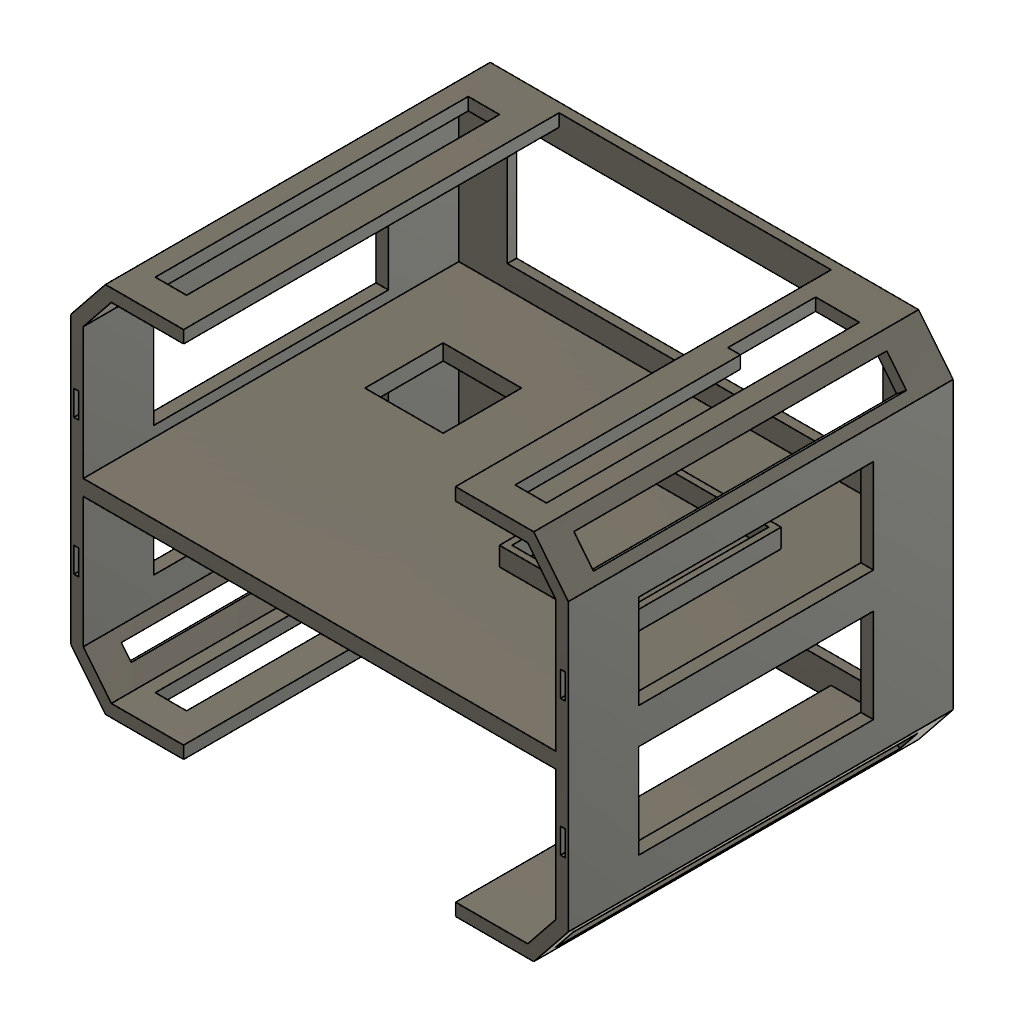
CAD_PicoHead (Autodesk Fusion 360 archive; units mm, degrees)
design "Side"
part number: 2026-11-01-21-09-07-078
Autodesk Fusion 360 part; units mm, degrees
(part 1 of 2)
sketch "Sketch1" plane through (0, 0, 0) normal (0, 0, 1) x (1, 0, 0)
  line L0 (31.9907, 26.2881) -> (20.9421, 12.4971)
  line L1 (31.9907, 26.2881) -> (31.9907, 117.6911)
  line L2 (31.9907, 117.6911) -> (20.9421, 131.4821)
  line L3 (20.9421, 131.4821) -> (-4.0579, 131.4821)
  line L4 (20.9614, 12.4971) -> (-115.9606, 12.4971)
  line L5 (-115.9606, 12.4971) -> (-127.0093, 26.2881)
  line L6 (-127.0093, 26.2881) -> (-127.0093, 117.6911)
  line L7 (-127.0093, 117.6911) -> (-115.9606, 131.4821)
  line L8 (-90.9606, 131.4821) -> (-115.9606, 131.4821)
  line L9 (-90.9606, 127.4821) -> (-114.0398, 127.4821)
  line L10 (-123.0093, 116.2864) -> (-114.0398, 127.4821)
  line L11 (-123.0093, 27.6928) -> (-123.0093, 116.2864)
  line L12 (-114.0398, 16.4971) -> (-123.0093, 27.6928)
  line L13 (19.0213, 16.4971) -> (-114.0398, 16.4971)
  line L14 (20.9614, 131.4821) -> (20.9614, 131.4579)
  line L15 (-90.9606, 131.4821) -> (-90.9606, 127.4821)
  line L16 (19.0213, 127.4821) -> (-4.0579, 127.4821)
  line L17 (27.9907, 116.2864) -> (19.0213, 127.4821)
  line L18 (27.9907, 27.6928) -> (27.9907, 116.2864)
  line L19 (27.9907, 27.6928) -> (19.0213, 16.4971)
  line L20 (-4.0579, 131.4821) -> (-4.0579, 127.4821)
  dimension "d35" = 17.671
  dimension "d36" = 17.671
  dimension "d37" = 141.3
  dimension "d38" = 141.3
  dimension "d39" = 25
  dimension "d79" = 17.671
  dimension "d83" = 128.7
  dimension "d84" = 91.403
  dimension "d85" = 25
  dimension "d138" = 159
  dimension "d140" = 4
  dimension "d141" = 4
  dimension "d142" = 4
  dimension "d143" = 4
  dimension "d144" = 4
  dimension "d145" = 4
  dimension "d146" = 4
  dimension "d147" = 4
  dimension "d148" = 4
  constraint vertical L1
  constraint perpendicular L1 L3
  constraint horizontal L4
  constraint perpendicular L3 L14
  constraint perpendicular L9 L15
  constraint coincident L2 L14.end
  constraint perpendicular L16 L20
  measures "d35" distance of L1.end L2.end
  measures "d36" distance of L0.end L0.start
  measures "d37" angle of L0 L1
  measures "d38" angle of L1 L2
  measures "d39" distance of L3.end L2.end
  measures "d79" distance of L4.end L5.end
  measures "d83" angle of L4 L5
  measures "d84" distance of L5.end L6.end
  measures "d85" distance of L7.end L8.start
  measures "d138" distance of L1 L6
  measures "d140" distance of L8 L9
  measures "d141" distance of L7 L10
  measures "d142" distance of L6 L11
  measures "d143" distance of L5 L12
  measures "d144" distance of L4 L13
  measures "d145" distance of L3 L16
  measures "d146" distance of L2 L17
  measures "d147" distance of L1 L18
  measures "d148" distance of L0 L19
extrude "Extrude1" add sketch "Sketch1" along normal blind 120
sketch "Sketch12" plane through (-127.0093, 0, 0) normal (-1, 0, 0) x (0, 0, 1)
  line L0 (0, 117.6911) -> (0, 26.2881)
  line L1 (0, 26.2881) -> (120, 26.2881)
  line L2 (120, 26.2881) -> (120, 117.6911)
  line L3 (120, 117.6911) -> (0, 117.6911)
  line L4 (22.5, 107.6911) -> (97.5, 107.6911)
  line L5 (97.5, 107.6911) -> (97.5, 77.6911)
  line L6 (97.5, 77.6911) -> (22.5, 77.6911)
  line L7 (22.5, 77.6911) -> (22.5, 107.6911)
  line L8 (60, 117.6911) -> (60, 26.2881) construction
  line L9 (97.5, 66.2881) -> (22.5, 66.2881)
  line L10 (22.5, 66.2881) -> (22.5, 36.2881)
  line L11 (22.5, 36.2881) -> (97.5, 36.2881)
  line L12 (97.5, 36.2881) -> (97.5, 66.2881)
  dimension "d87" = 75
  dimension "d88" = 30
  dimension "d89" = 37.5
  dimension "d90" = 75
  dimension "d91" = 30
  dimension "d93" = 10
  dimension "d94" = 10
  constraint horizontal L4
  constraint vertical L5
  constraint horizontal L6
  constraint vertical L7
  constraint midpoint L3 L8.start
  constraint midpoint L1 L8.end
  constraint horizontal L9
  constraint vertical L10
  constraint horizontal L11
  constraint vertical L12
  measures "d87" distance of L4.start L4.end
  measures "d88" distance of L4.start L6.end
  measures "d89" distance of L5 L8
  measures "d90" distance of L9.start L9.end
  measures "d91" distance of L9.start L11.end
  measures "d93" distance of L3 L4
  measures "d94" distance of L1 L11
extrude "Extrude11" cut sketch "Sketch12" against normal blind 33 contours L4 L5 L6 L7 | L9 L10 L11 L12
sketch "Sketch13" plane through (31.9907, 0, 0) normal (1, 0, 0) x (0, 0, -1)
  line L0 (0, 26.2881) -> (0, 117.6911)
  line L1 (0, 117.6911) -> (-120, 117.6911)
  line L2 (-120, 117.6911) -> (-120, 26.2881)
  line L3 (-120, 26.2881) -> (0, 26.2881)
  line L4 (-60, 117.6911) -> (-60, 26.2881) construction
  line L5 (-97.5, 107.6911) -> (-22.5, 107.6911)
  line L6 (-22.5, 107.6911) -> (-22.5, 77.6911)
  line L7 (-22.5, 77.6911) -> (-97.5, 77.6911)
  line L8 (-97.5, 77.6911) -> (-97.5, 107.6911)
  line L9 (-22.5, 36.2881) -> (-97.5, 36.2881)
  line L10 (-97.5, 36.2881) -> (-97.5, 66.2881)
  line L11 (-97.5, 66.2881) -> (-22.5, 66.2881)
  line L12 (-22.5, 66.2881) -> (-22.5, 36.2881)
  line L13 (0, 26.2881) -> (0, 117.6911)
  line L14 (0, 117.6911) -> (-120, 117.6911)
  line L15 (-120, 117.6911) -> (-120, 26.2881)
  line L16 (-120, 26.2881) -> (0, 26.2881)
  dimension "d97" = 75
  dimension "d98" = 30
  dimension "d99" = 37.5
  dimension "d100" = 10
  dimension "d101" = 75
  dimension "d102" = 37.5
  dimension "d103" = 10
  dimension "d104" = 30
  constraint midpoint L1 L4.start
  constraint midpoint L3 L4.end
  constraint horizontal L5
  constraint vertical L6
  constraint horizontal L7
  constraint vertical L8
  constraint horizontal L9
  constraint vertical L10
  constraint horizontal L11
  constraint vertical L12
  measures "d97" distance of L5.start L5.end
  measures "d98" distance of L5.start L7.end
  measures "d99" distance of L4 L6
  measures "d100" distance of L1 L5
  measures "d101" distance of L9.start L9.end
  measures "d102" distance of L4 L12
  measures "d103" distance of L3 L9
  measures "d104" distance of L9.start L11.end
extrude "Extrude12" cut sketch "Sketch13" against normal blind 20 contours L5 L6 L7 L8 | L9 L10 L11 L12
sketch "Sketch14" plane through (0, 131.4821, 0) normal (0, 1, 0) x (-1, 0, 0)
  line L0 (-45.9614, 0) -> (-20.9614, 0)
  line L1 (-20.9614, 0) -> (-20.9614, 120)
  line L2 (-20.9614, 120) -> (-45.9614, 120)
  line L3 (110, 10) -> (100, 10)
  line L4 (100, 10) -> (100, 110)
  line L5 (100, 110) -> (110, 110)
  line L6 (110, 110) -> (110, 10)
  line L7 (-20.9421, 0) -> (4.0579, 0)
  line L8 (4.0579, 0) -> (4.0579, 120)
  line L9 (4.0579, 120) -> (-20.9421, 120)
  line L10 (-20.9421, 120) -> (-20.9421, 0)
  line L11 (-5, 10) -> (-15, 10)
  line L12 (-15, 10) -> (-15, 110)
  line L13 (-15, 110) -> (-5, 110)
  line L14 (-5, 110) -> (-5, 10)
  constraint horizontal L3
  constraint vertical L4
  constraint horizontal L5
  constraint vertical L6
  constraint horizontal L11
  constraint vertical L12
  constraint horizontal L13
  constraint vertical L14
extrude "Extrude13" cut sketch "Sketch14" against normal blind 10 contours L3 L4 L5 L6 | L11 L12 L13 L14
sketch "Sketch15" plane through (76.913, 61.6189, 0) normal (0.78043, 0.625243, 0) x (0, 0, -1)
  line L0 (0, 56.2046) -> (0, 73.8756)
  line L1 (0, 73.8756) -> (-120, 73.8756)
  line L2 (-120, 73.8756) -> (-120, 56.2046)
  line L3 (-120, 56.2046) -> (0, 56.2046)
  line L4 (0, 71.8477) -> (0, 89.5187)
  line L5 (0, 89.5187) -> (-120, 89.5187)
  line L6 (-120, 89.5187) -> (-120, 71.8477)
  line L7 (-120, 71.8477) -> (0, 71.8477)
  line L8 (-110, 85) -> (-10, 85)
  line L9 (-10, 85) -> (-10, 75)
  line L10 (-10, 75) -> (-110, 75)
  line L11 (-110, 75) -> (-110, 85)
  constraint horizontal L8
  constraint vertical L9
  constraint horizontal L10
  constraint vertical L11
extrude "Extrude14" cut sketch "Sketch15" against normal blind 40 contours L8 L9 L10 L11
sketch "Sketch16" plane through (-134.7861, 107.984, 0) normal (-0.78043, 0.625243, 0) x (0, 0, 1)
  line L0 (0, 30.1091) -> (0, 12.4381)
  line L1 (0, 12.4381) -> (120, 12.4381)
  line L2 (120, 12.4381) -> (120, 30.1091)
  line L3 (120, 30.1091) -> (0, 30.1091)
  line L4 (10, 25) -> (110, 25)
  line L5 (110, 25) -> (110, 15)
  line L6 (110, 15) -> (10, 15)
  line L7 (10, 15) -> (10, 25)
  constraint horizontal L4
  constraint vertical L5
  constraint horizontal L6
  constraint vertical L7
extrude "Extrude15" cut sketch "Sketch16" against normal blind 20 contours L4 L5 L6 L7
sketch "Sketch17" plane through (6.6572, -5.3334, 0) normal (0.78043, -0.625243, 0) x (0, 0, -1)
  line L0 (0, 38.4901) -> (0, 56.1611)
  line L1 (0, 56.1611) -> (-120, 56.1611)
  line L2 (-120, 56.1611) -> (-120, 38.4901)
  line L3 (-120, 38.4901) -> (0, 38.4901)
  line L4 (0, 22.847) -> (0, 40.518)
  line L5 (0, 40.518) -> (-120, 40.518)
  line L6 (-120, 40.518) -> (-120, 22.847)
  line L7 (-120, 22.847) -> (0, 22.847)
  line L8 (-115, 35) -> (-5, 35)
  line L9 (-5, 35) -> (-5, 26)
  line L10 (-5, 26) -> (-115, 26)
  line L11 (-115, 26) -> (-115, 35)
  constraint horizontal L8
  constraint vertical L9
  constraint horizontal L10
  constraint vertical L11
extrude "Extrude16" cut sketch "Sketch17" against normal blind 20 contours L8 L9 L10 L11
sketch "Sketch18" plane through (-64.5303, -51.6985, 0) normal (-0.78043, -0.625243, 0) x (0, 0, 1)
  line L0 (0, 99.9276) -> (0, 82.2566)
  line L1 (0, 82.2566) -> (120, 82.2566)
  line L2 (120, 82.2566) -> (120, 99.9276)
  line L3 (120, 99.9276) -> (0, 99.9276)
  line L4 (10, 95) -> (110, 95)
  line L5 (110, 95) -> (110, 90)
  line L6 (110, 90) -> (10, 90)
  line L7 (10, 90) -> (10, 95)
  constraint horizontal L4
  constraint vertical L5
  constraint horizontal L6
  constraint vertical L7
extrude "Extrude17" cut sketch "Sketch18" against normal blind 25 contours L4 L5 L6 L7
sketch "Sketch19" plane through (0, 0, 0) normal (0, 0, -1) x (-1, 0, 0)
  line L0 (-20.9421, 12.4971) -> (115.9606, 12.4971)
  line L1 (115.9606, 12.4971) -> (127.0093, 26.2881)
  line L2 (127.0093, 26.2881) -> (127.0093, 117.6911)
  line L3 (127.0093, 117.6911) -> (115.9606, 131.4821)
  line L4 (115.9606, 131.4821) -> (90.9606, 131.4821)
  line L5 (90.9606, 131.4821) -> (90.9606, 127.4821)
  line L6 (90.9606, 127.4821) -> (114.0398, 127.4821)
  line L7 (114.0398, 127.4821) -> (123.0093, 116.2864)
  line L8 (123.0093, 116.2864) -> (123.0093, 27.6928)
  line L9 (123.0093, 27.6928) -> (114.0398, 16.4971)
  line L10 (114.0398, 16.4971) -> (-19.0213, 16.4971)
  line L11 (-45.9614, 131.4821) -> (115.9606, 131.4821)
  line L12 (-31.9907, 117.6911) -> (-31.9907, 26.2881)
  line L13 (-31.9907, 26.2881) -> (-20.9421, 12.4971)
  line L14 (-19.0213, 16.4971) -> (-27.9907, 27.6928)
  line L15 (-27.9907, 27.6928) -> (-27.9907, 116.2864)
  line L16 (-27.9907, 116.2864) -> (-19.0213, 127.4821)
  line L17 (-19.0213, 127.4821) -> (4.0579, 127.4821)
  line L18 (4.0579, 127.4821) -> (4.0579, 131.4821)
  line L19 (4.0579, 131.4821) -> (-20.9421, 131.4821)
  line L20 (-20.9421, 131.4821) -> (-31.9907, 117.6911)
  constraint coincident L3.end L4.start
extrude "Extrude18" add sketch "Sketch19" along normal blind 3
sketch "Sketch20" plane through (0, 12.4971, 0) normal (0, -1, 0) x (1, 0, 0)
  line L0 (20.9421, 120) -> (-115.9606, 120)
  line L1 (-115.9606, 120) -> (-115.9606, -3)
  line L2 (-115.9606, -3) -> (20.9421, -3)
  line L3 (-115.9606, 120) -> (-90.9606, 120)
  line L4 (-90.9606, 120) -> (-90.9606, -3)
  line L5 (-90.9606, -3) -> (-115.9606, -3)
  line L6 (-115.9606, -3) -> (-115.9606, 120)
  line L7 (20.9421, 120) -> (-4.0579, 120)
  line L8 (-4.0579, 120) -> (-4.0579, -3)
  line L9 (-4.0579, -3) -> (20.9421, -3)
  line L10 (20.9421, -3) -> (20.9421, 120)
  line L11 (-115.9606, -3) -> (45.9614, -3)
  line L12 (45.9614, -3) -> (45.9614, 0)
  line L13 (45.9614, 0) -> (-115.9606, 0)
  line L14 (-115.9606, 0) -> (-115.9606, -3)
  line L15 (20.9421, -3) -> (20.9421, 120)
  dimension "d119" = 25
  dimension "d120" = 25
  dimension "d121" = 3
  constraint horizontal L3
  constraint vertical L4
  constraint horizontal L5
  constraint vertical L6
  constraint coincident L2 L4.end
  constraint coincident L0.end L1.start
  constraint horizontal L7
  constraint vertical L8
  constraint horizontal L9
  constraint vertical L10
  constraint coincident L2 L8.end
  constraint coincident L0.start L7.start
  constraint horizontal L11
  constraint vertical L12
  constraint horizontal L13
  constraint vertical L14
  constraint coincident L1.end L2.start
  measures "d119" distance of L0.end L3.end
  measures "d120" distance of L0.start L7.end
  measures "d121" distance of L1.end L13.end
extrude "Extrude19" cut sketch "Sketch20" against normal blind 5 contours L0 L4 L8 L13
sketch "Sketch21" plane through (0, 12.4971, 0) normal (0, -1, 0) x (1, 0, 0)
  line L0 (-4.0579, 120) -> (-4.0579, 0)
  line L1 (-4.0579, 0) -> (-90.9606, 0)
  line L2 (-90.9606, 0) -> (-90.9606, 120)
  line L3 (-90.9606, 120) -> (-115.9606, 120)
  line L4 (-115.9606, 120) -> (-115.9606, -3)
  line L5 (-115.9606, -3) -> (20.9421, -3)
  line L6 (20.9421, 120) -> (-4.0579, 120)
  line L7 (-110, 110) -> (-100, 110)
  line L8 (-100, 110) -> (-100, 10)
  line L9 (-100, 10) -> (-110, 10)
  line L10 (-110, 10) -> (-110, 110)
  line L11 (30, 110) -> (40, 110)
  line L12 (40, 110) -> (40, 10)
  line L13 (40, 10) -> (30, 10)
  line L14 (30, 10) -> (30, 110)
  line L15 (20.9421, -3) -> (20.9421, 120)
  constraint horizontal L7
  constraint vertical L8
  constraint horizontal L9
  constraint vertical L10
  constraint horizontal L11
  constraint vertical L12
  constraint horizontal L13
  constraint vertical L14
extrude "Extrude20" cut sketch "Sketch21" against normal blind 5 contours L7 L8 L9 L10 | L11 L12 L13 L14
sketch "Sketch22" plane through (31.9907, 0, 0) normal (-1, 0, 0) x (0, 0, 1)
  line L0 (22.5, 77.6911) -> (22.5, 107.6911)
  line L1 (22.5, 107.6911) -> (97.5, 107.6911)
  line L2 (97.5, 107.6911) -> (97.5, 77.6911)
  line L3 (97.5, 77.6911) -> (22.5, 77.6911)
  line L4 (97.5, 66.2881) -> (97.5, 36.2881)
  line L5 (97.5, 36.2881) -> (22.5, 36.2881)
  line L6 (22.5, 36.2881) -> (22.5, 66.2881)
  line L7 (22.5, 66.2881) -> (97.5, 66.2881)
  line L8 (0, 116.2864) -> (0, 27.6928)
  line L9 (0, 27.6928) -> (120, 27.6928)
  line L10 (120, 27.6928) -> (120, 116.2864)
  line L11 (120, 116.2864) -> (0, 116.2864)
  line L12 (120, 74.2881) -> (0, 74.2881)
  line L13 (0, 74.2881) -> (0, 69.2881)
  line L14 (0, 69.2881) -> (120, 69.2881)
  line L15 (120, 69.2881) -> (120, 74.2881)
  line L16 (120, 27.6928) -> (0, 27.6928)
  line L17 (0, 27.6928) -> (0, 36.2881)
  line L18 (0, 36.2881) -> (120, 36.2881)
  line L19 (120, 36.2881) -> (120, 27.6928)
  line L20 (22.5, 107.6911) -> (22.5, 77.6911)
  line L21 (22.5, 77.6911) -> (97.5, 77.6911)
  line L22 (97.5, 77.6911) -> (97.5, 107.6911)
  line L23 (97.5, 36.2881) -> (97.5, 66.2881)
  line L24 (97.5, 66.2881) -> (22.5, 66.2881)
  line L25 (22.5, 66.2881) -> (22.5, 36.2881)
  line L26 (-3, 117.6911) -> (120, 117.6911)
  line L27 (120, 117.6911) -> (120, 26.2881)
  line L28 (120, 26.2881) -> (-3, 26.2881)
  line L29 (-3, 26.2881) -> (-3, 117.6911)
  line L30 (97.5, 107.6911) -> (22.5, 107.6911)
  line L31 (22.5, 36.2881) -> (97.5, 36.2881)
  dimension "d128" = 5
  dimension "d129" = 3
  constraint horizontal L12
  constraint vertical L13
  constraint horizontal L14
  constraint vertical L15
  constraint coincident L8 L13.end
  constraint coincident L10 L12.start
  constraint horizontal L16
  constraint vertical L17
  constraint horizontal L18
  constraint vertical L19
  constraint coincident L8 L17.end
  constraint coincident L9.end L10.start
  measures "d128" distance of L12.start L14.end
  measures "d129" distance of L4.start L14
extrude "Extrude21" add sketch "Sketch22" along normal blind 155 contours L8 L10 L12 L13 L14 L15 L27
sketch "Sketch23" plane through (0, 74.2881, 0) normal (0, 1, 0) x (-1, 0, 0)
  line L0 (123.0093, 0) -> (123.0093, 120)
  line L1 (123.0093, 120) -> (-27.9907, 120)
  line L2 (-27.9907, 0) -> (123.0093, 0)
  line L3 (30.0093, 30) -> (-5.9907, 30)
  line L4 (-5.9907, 30) -> (-5.9907, 76)
  line L5 (-5.9907, 76) -> (30.0093, 76)
  line L6 (30.0093, 76) -> (30.0093, 30)
  line L7 (32.0093, 78) -> (32.0093, 28)
  line L8 (32.0093, 28) -> (-7.9907, 28)
  line L9 (-7.9907, 28) -> (-7.9907, 78)
  line L10 (-7.9907, 78) -> (32.0093, 78)
  line L11 (-27.9907, 120) -> (-27.9907, 0)
  dimension "d130" = 36
  dimension "d131" = 46
  dimension "d132" = -2
  dimension "d149" = 20
  constraint horizontal L3
  constraint vertical L4
  constraint horizontal L5
  constraint vertical L6
  measures "d130" distance of L3.start L3.end
  measures "d131" distance of L3.start L5.end
  measures "d149" distance of L9 L11
extrude "Extrude22" add sketch "Sketch23" along normal blind 6 contours L7 L8 L9 L10
sketch "Sketch24" plane through (0, 74.2881, 0) normal (0, 1, 0) x (-1, 0, 0)
  line L0 (123.0093, 0) -> (123.0093, 120)
  line L1 (123.0093, 120) -> (-27.9907, 120)
  line L2 (-27.9907, 0) -> (123.0093, 0)
  line L3 (-7.9907, 78) -> (32.0093, 78)
  line L4 (32.0093, 78) -> (32.0093, 28)
  line L5 (32.0093, 28) -> (-7.9907, 28)
  line L6 (-7.9907, 28) -> (-7.9907, 78)
  line L7 (103.0093, 25) -> (78.0093, 25)
  line L8 (78.0093, 25) -> (78.0093, 50)
  line L9 (78.0093, 50) -> (103.0093, 50)
  line L10 (103.0093, 50) -> (103.0093, 25)
  line L11 (-27.9907, 120) -> (-27.9907, 0)
  dimension "d150" = 20
  constraint horizontal L7
  constraint vertical L8
  constraint horizontal L9
  constraint vertical L10
  measures "d150" distance of L0 L10
extrude "Extrude23" cut sketch "Sketch24" against normal blind 15 contours L7 L8 L9 L10
sketch "Sketch25" plane through (0, 0, 0) normal (0, 0, 1) x (1, 0, 0)
  line L0 (-123.0093, 74.2881) -> (27.9907, 74.2881)
  line L1 (27.9907, 74.2881) -> (27.9907, 116.2864)
  line L2 (27.9907, 116.2864) -> (19.0213, 127.4821)
  line L3 (19.0213, 127.4821) -> (-4.0579, 127.4821)
  line L4 (-4.0579, 127.4821) -> (-4.0579, 131.4821)
  line L5 (-4.0579, 131.4821) -> (-90.9606, 131.4821)
  line L6 (-90.9606, 131.4821) -> (-90.9606, 127.4821)
  line L7 (-90.9606, 127.4821) -> (-114.0398, 127.4821)
  line L8 (-114.0398, 127.4821) -> (-123.0093, 116.2864)
  line L9 (-123.0093, 116.2864) -> (-123.0093, 74.2881)
  line L10 (-107.5093, 121.4821) -> (12.4907, 121.4821)
  line L11 (12.4907, 121.4821) -> (12.4907, 81.4821)
  line L12 (12.4907, 81.4821) -> (-107.5093, 81.4821)
  line L13 (-107.5093, 81.4821) -> (-107.5093, 121.4821)
  line L14 (-107.5093, 62.4971) -> (12.4907, 62.4971)
  line L15 (12.4907, 62.4971) -> (12.4907, 22.4971)
  line L16 (12.4907, 22.4971) -> (-107.5093, 22.4971)
  line L17 (-107.5093, 22.4971) -> (-107.5093, 62.4971)
  line L18 (27.9907, 27.6928) -> (27.9907, 69.2881)
  point P0 (-4.0579, 12.4971)
  dimension "d151" = 40
  dimension "d152" = 120
  dimension "d153" = 40
  dimension "d154" = 120
  dimension "d155" = 10
  dimension "d156" = 10
  dimension "d159" = 15.5
  dimension "d160" = 15.5
  constraint horizontal L10
  constraint vertical L11
  constraint horizontal L12
  constraint vertical L13
  constraint horizontal L14
  constraint vertical L15
  constraint horizontal L16
  constraint vertical L17
  measures "d151" distance of L14.start L16.end
  measures "d152" distance of L15.end L16.end
  measures "d153" distance of L10.start L12.end
  measures "d154" distance of L10.start L10.end
  measures "d155" distance of L5 L10
  measures "d156" distance of L16 P0
  measures "d159" distance of L1 L11
  measures "d160" distance of L15 L18
extrude "Extrude24" cut sketch "Sketch25" against normal blind 20 contours L10 L11 L12 L13 | L14 L15 L16 L17
sketch "Sketch26" plane through (0, 131.4821, 0) normal (0, 1, 0) x (-1, 0, 0)
  line L0 (100, 10) -> (100, 110)
  line L1 (100, 110) -> (110, 110)
  line L2 (110, 110) -> (110, 10)
  line L3 (110, 10) -> (100, 10)
  line L4 (-15, 10) -> (-15, 110)
  line L5 (-15, 110) -> (-5, 110)
  line L6 (-5, 110) -> (-5, 10)
  line L7 (-5, 10) -> (-15, 10)
  line L8 (4.0579, 0) -> (4.0579, 120)
  line L9 (4.0579, 120) -> (-20.9421, 120)
  line L10 (-20.9421, 120) -> (-20.9421, -3)
  line L11 (-20.9421, -3) -> (115.9606, -3)
  line L12 (115.9606, -3) -> (115.9606, 120)
  line L13 (115.9606, 120) -> (90.9606, 120)
  line L14 (90.9606, 120) -> (90.9606, 0)
  line L15 (90.9606, 0) -> (4.0579, 0)
  line L16 (-15, 10) -> (-1, 10)
  line L17 (-1, 10) -> (-1, 38)
  line L18 (-1, 38) -> (-15, 38)
  line L19 (-15, 38) -> (-15, 10)
  dimension "d161" = 14
  dimension "d162" = 28
  constraint horizontal L16
  constraint vertical L17
  constraint horizontal L18
  constraint vertical L19
  constraint coincident L4.start L7.end
  measures "d161" distance of L4.start L16.end
  measures "d162" distance of L4.start L18.end
extrude "Extrude25" cut sketch "Sketch26" against normal blind 9 contours L6 L16 L17 L18
sketch "Sketch27" plane through (0, 0, 120) normal (0, 0, 1) x (1, 0, 0)
  line L0 (-90.9606, 12.4971) -> (-90.9606, 16.4971)
  line L1 (-90.9606, 16.4971) -> (-114.0398, 16.4971)
  line L2 (-114.0398, 16.4971) -> (-123.0093, 27.6928)
  line L3 (-123.0093, 27.6928) -> (-123.0093, 69.2881)
  line L4 (-123.0093, 69.2881) -> (27.9907, 69.2881)
  line L5 (27.9907, 69.2881) -> (27.9907, 27.6928)
  line L6 (27.9907, 27.6928) -> (19.0213, 16.4971)
  line L7 (19.0213, 16.4971) -> (-4.0579, 16.4971)
  line L8 (-4.0579, 16.4971) -> (-4.0579, 12.4971)
  line L9 (-4.0579, 12.4971) -> (20.9421, 12.4971)
  line L10 (20.9421, 12.4971) -> (31.9907, 26.2881)
  line L11 (31.9907, 26.2881) -> (31.9907, 117.6911)
  line L12 (31.9907, 117.6911) -> (20.9421, 131.4821)
  line L13 (20.9421, 131.4821) -> (-4.0579, 131.4821)
  line L14 (-4.0579, 131.4821) -> (-4.0579, 127.4821)
  line L15 (-4.0579, 127.4821) -> (19.0213, 127.4821)
  line L16 (19.0213, 127.4821) -> (27.9907, 116.2864)
  line L17 (27.9907, 116.2864) -> (27.9907, 74.2881)
  line L18 (27.9907, 74.2881) -> (-123.0093, 74.2881)
  line L19 (-123.0093, 74.2881) -> (-123.0093, 116.2864)
  line L20 (-123.0093, 116.2864) -> (-114.0398, 127.4821)
  line L21 (-114.0398, 127.4821) -> (-90.9606, 127.4821)
  line L22 (-90.9606, 127.4821) -> (-90.9606, 131.4821)
  line L23 (-90.9606, 131.4821) -> (-115.9606, 131.4821)
  line L24 (-115.9606, 131.4821) -> (-127.0093, 117.6911)
  line L25 (-127.0093, 117.6911) -> (-127.0093, 26.2881)
  line L26 (-127.0093, 26.2881) -> (-115.9606, 12.4971)
  line L27 (-115.9606, 12.4971) -> (-90.9606, 12.4971)
  line L28 (29.4907, 97.6911) -> (30.9907, 97.6911)
  line L29 (30.9907, 97.6911) -> (30.9907, 89.6911)
  line L30 (30.9907, 89.6911) -> (29.4907, 89.6911)
  line L31 (29.4907, 89.6911) -> (29.4907, 97.6911)
  line L32 (29.4907, 54.2881) -> (30.9907, 54.2881)
  line L33 (30.9907, 54.2881) -> (30.9907, 46.2881)
  line L34 (30.9907, 46.2881) -> (29.4907, 46.2881)
  line L35 (29.4907, 46.2881) -> (29.4907, 54.2881)
  line L36 (-126.0093, 97.6911) -> (-124.5093, 97.6911)
  line L37 (-124.5093, 97.6911) -> (-124.5093, 89.6911)
  line L38 (-124.5093, 89.6911) -> (-126.0093, 89.6911)
  line L39 (-126.0093, 89.6911) -> (-126.0093, 97.6911)
  line L40 (-126, 46.2881) -> (-124.5, 46.2881)
  line L41 (-124.5, 46.2881) -> (-124.5, 54.2881)
  line L42 (-124.5, 54.2881) -> (-126, 54.2881)
  line L43 (-126, 54.2881) -> (-126, 46.2881)
  dimension "d165" = 1.5
  dimension "d166" = 8
  dimension "d167" = 1
  dimension "d169" = 1.5
  dimension "d170" = 8
  dimension "d171" = 1
  dimension "d172" = 20
  dimension "d173" = 1.5
  dimension "d174" = 8
  dimension "d175" = 1
  dimension "d177" = 1.5
  dimension "d178" = 8
  dimension "d179" = 20
  dimension "d182" = 20
  dimension "d183" = 20
  constraint horizontal L28
  constraint vertical L29
  constraint horizontal L30
  constraint vertical L31
  constraint horizontal L32
  constraint vertical L33
  constraint horizontal L34
  constraint vertical L35
  constraint horizontal L36
  constraint vertical L37
  constraint horizontal L38
  constraint vertical L39
  constraint horizontal L40
  constraint vertical L41
  constraint horizontal L42
  constraint vertical L43
  measures "d165" distance of L28.start L28.end
  measures "d166" distance of L28.start L30.end
  measures "d167" distance of L11 L29
  measures "d169" distance of L32.start L32.end
  measures "d170" distance of L32.start L34.end
  measures "d171" distance of L11 L33.end
  measures "d172" vertical distance of L10.end L33.end
  measures "d173" distance of L36.start L36.end
  measures "d174" distance of L36.start L38.end
  measures "d175" distance of L25 L39
  measures "d177" distance of L40.start L40.end
  measures "d178" distance of L40.start L42.end
  measures "d179" vertical distance of L25.end L40.start
  measures "d182" vertical distance of L24.end L36.end
  measures "d183" vertical distance of L11.end L28.end
extrude "Extrude26" cut sketch "Sketch27" against normal blind 9 contours L28 L29 L30 L31 | L32 L33 L34 L35 | L36 L37 L38 L39 | L40 L41 L42 L43
equation "d89 = ( 75 / 2 ) * 1 mm"
equation "d99 = ( 75 / 2 ) * 1 mm"
equation "d102 = ( 75 / 2 ) * 1 mm"
equation "d159 = ( 31 / 2 ) * 1 mm"
equation "d160 = ( 31 / 2 ) * 1 mm"

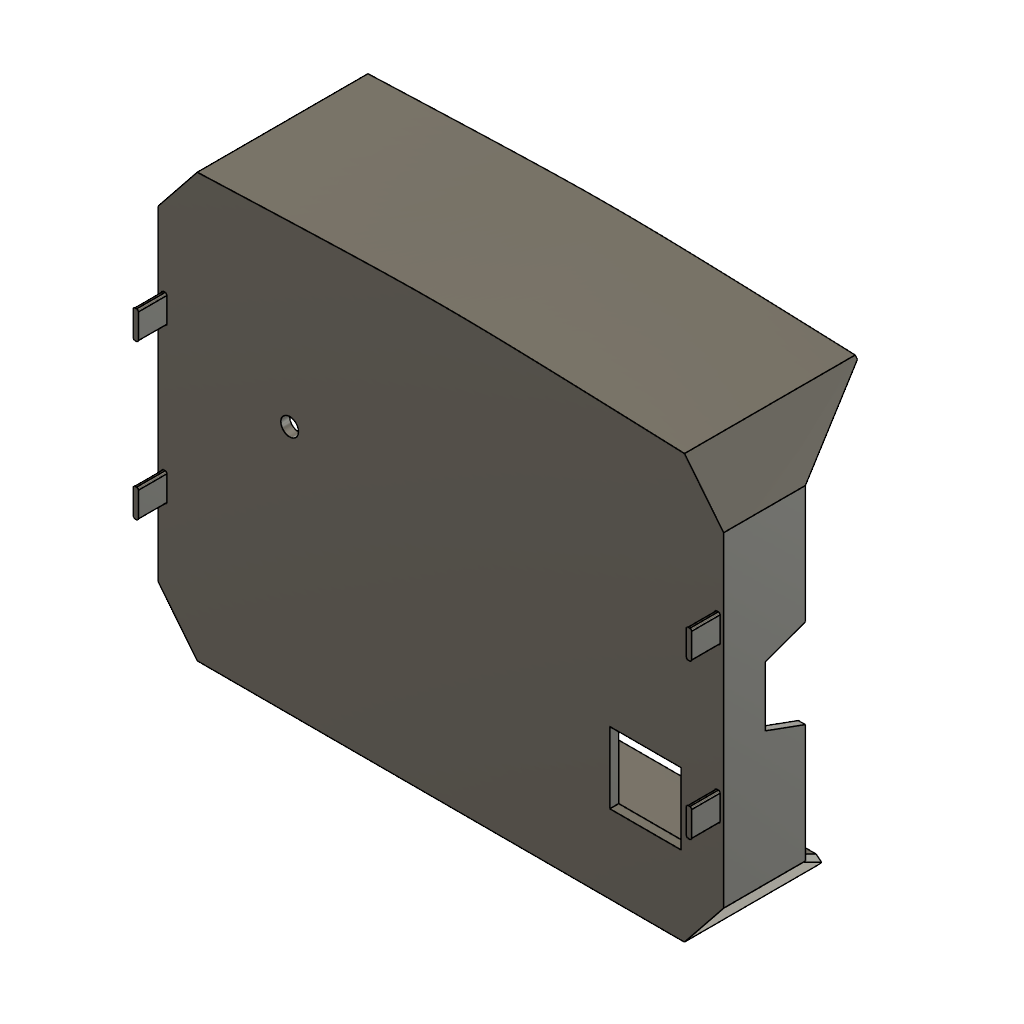
design "PICO_Face"
part number: 2026-11-01-18-38-38-667
Autodesk Fusion 360 part; units mm, degrees
sketch "Sketch1" plane through (0, 0, 0) normal (0, 0, 1) x (1, 0, 0)
  line L0 (10, 0) -> (145, 0)
  line L1 (155, 12.5) -> (155, 102.5)
  line L2 (0, 102.5) -> (0, 12.5)
  line L3 (0, 102.5) -> (155, 102.5)
  line L4 (155, 102.5) -> (155, 12.5)
  line L5 (155, 12.5) -> (0, 12.5)
  line L6 (0, 12.5) -> (0, 102.5)
  line L7 (10, 115) -> (0, 102.5)
  line L8 (145, 115) -> (155, 102.5)
  line L9 (0, 12.5) -> (10, 0)
  line L10 (145, 0) -> (145, 12.5) construction
  line L11 (155, 12.5) -> (145, 0)
  line L12 (17.5, 92.5) -> (67.5, 92.5) construction
  line L13 (67.5, 92.5) -> (67.5, 60.5) construction
  line L14 (67.5, 60.5) -> (17.5, 60.5) construction
  line L15 (17.5, 60.5) -> (17.5, 92.5) construction
  line L16 (137.5, 92.5) -> (87.5, 92.5) construction
  line L17 (87.5, 92.5) -> (87.5, 60.5) construction
  line L18 (87.5, 60.5) -> (137.5, 60.5) construction
  line L19 (137.5, 60.5) -> (137.5, 92.5) construction
  line L20 (10, 115) -> (145, 115) construction
  spline S0 degree 2 poles (10, 115) (77.5, 117.6157) (145, 115) knots 0 0 0 13.5057 13.5057 13.5057 weights 1 3 1
  line L21 (22.5, 50.5) -> (72.5, 50.5) construction
  line L22 (72.5, 50.5) -> (72.5, 18.5) construction
  line L23 (72.5, 18.5) -> (22.5, 18.5) construction
  line L24 (22.5, 18.5) -> (22.5, 50.5) construction
  line L25 (85, 50.5) -> (135, 50.5) construction
  line L26 (135, 50.5) -> (135, 18.5) construction
  line L27 (135, 18.5) -> (85, 18.5) construction
  line L28 (85, 18.5) -> (85, 50.5) construction
  dimension "d5" = 90
  dimension "d6" = 135
  dimension "d7" = 10
  dimension "d10" = 10
  dimension "d11" = 50
  dimension "d12" = 32
  dimension "d13" = 50
  dimension "d14" = 32
  dimension "d18" = 12.5
  dimension "d20" = 10
  dimension "d21" = 10
  dimension "d22" = 50
  dimension "d23" = 32
  dimension "d24" = 50
  dimension "d25" = 32
  dimension "d26" = 10
  dimension "d27" = 10
  dimension "d28" = 20
  dimension "d29" = 17.5
  dimension "d30" = 12.5
  dimension "d31" = 22.5
  constraint horizontal L0
  constraint vertical L1
  constraint vertical L2
  constraint horizontal L3
  constraint vertical L4
  constraint horizontal L5
  constraint vertical L6
  constraint coincident L5 L10.end
  constraint perpendicular L5 L10
  constraint horizontal L12
  constraint vertical L13
  constraint horizontal L14
  constraint vertical L15
  constraint horizontal L16
  constraint vertical L17
  constraint horizontal L18
  constraint vertical L19
  constraint parallel L3 L20
  constraint horizontal L21
  constraint vertical L22
  constraint horizontal L23
  constraint vertical L24
  constraint horizontal L25
  constraint vertical L26
  constraint horizontal L27
  constraint vertical L28
  measures "d5" distance of L3 L5
  measures "d6" distance of L7.start L8.start
  measures "d7" distance of L6 L7.start
  measures "d10" distance of L1 L10
  measures "d11" distance of L12.start L12.end
  measures "d12" distance of L12.start L14.end
  measures "d13" distance of L16.start L16.end
  measures "d14" distance of L16.start L18.end
  measures "d18" distance of L3 L20
  measures "d20" distance of L3 L12
  measures "d21" distance of L3 L16
  measures "d22" distance of L21.start L21.end
  measures "d23" distance of L21.start L23.end
  measures "d24" distance of L25.start L25.end
  measures "d25" distance of L25.start L27.end
  measures "d26" distance of L18 L25
  measures "d27" distance of L14 L21
  measures "d28" distance of L13 L17
  measures "d29" distance of L4 L19
  measures "d30" distance of L22 L28
  measures "d31" distance of L2 L24
extrude "Extrude1" add sketch "Sketch1" along normal blind 2.5
sketch "Sketch2" plane through (0, 0, 2.5) normal (0, 0, 1) x (1, 0, 0)
  line L0 (0, 12.5) -> (10, 0)
  line L1 (10, 0) -> (145, 0)
  line L2 (145, 0) -> (155, 12.5)
  line L3 (155, 12.5) -> (155, 102.5)
  line L4 (155, 102.5) -> (145, 115)
  spline S0 degree 2 poles (145, 115) (77.5, 117.6157) (10, 115) knots -13.5057 -13.5057 -13.5057 0 0 0 weights 1 3 1
  line L5 (10, 115) -> (0, 102.5)
  line L6 (0, 102.5) -> (0, 12.5)
  line L7 (-2, 103.2016) -> (-2, 11.7984)
  line L8 (-2, 11.7984) -> (9.0388, -2)
  line L9 (9.0388, -2) -> (145.9612, -2)
  line L10 (145.9612, -2) -> (157, 11.7984)
  line L11 (157, 11.7984) -> (157, 103.2016)
  line L12 (157, 103.2016) -> (145.9908, 116.9631)
  spline S1 degree 3 poles (145.9908, 116.9631) (145.6863, 116.9749) (145.3819, 116.9867) (145.0774, 116.9985) (138.5067, 117.2531) (133.3735, 117.448) (128.9839, 117.6117) (123.3639, 117.8212) (118.9847, 117.9786) (115.2269, 118.109) (110.0914, 118.2873) (106.1355, 118.4146) (102.7172, 118.5165) (98.1859, 118.6516) (94.6262, 118.7412) (91.4483, 118.8069) (86.738, 118.9044) (82.8964, 118.9491) (79.1064, 118.9596) (75.4974, 118.9695) (71.9821, 118.9477) (67.9652, 118.8866) (65.0372, 118.8421) (61.8549, 118.7768) (57.9877, 118.6763) (54.9693, 118.5979) (51.5444, 118.4985) (47.2448, 118.3599) (43.8313, 118.2498) (39.8791, 118.1155) (34.8319, 117.9345) (31.2439, 117.8059) (27.106, 117.6538) (21.9652, 117.4597) (18.5002, 117.3289) (14.5782, 117.1789) (9.9226, 116.9985) (9.6181, 116.9867) (9.3137, 116.9749) (9.0092, 116.9631) knots -13.536157 -13.536157 -13.536157 -13.536157 -13.5057 -13.5057 -13.5057 -12.848427 -12.848427 -12.848427 -12.006919 -12.006919 -12.006919 -10.856885 -10.856885 -10.856885 -9.332387 -9.332387 -9.332387 -7.072806 -7.072806 -7.072806 -4.921137 -4.921137 -4.921137 -3.352707 -3.352707 -3.352707 -2.128529 -2.128529 -2.128529 -1.156627 -1.156627 -1.156627 -0.465703 -0.465703 -0.465703 0 0 0 0.030457 0.030457 0.030457 0.030457
  line L13 (9.0092, 116.9631) -> (-2, 103.2016)
  line L14 (10, 115) -> (9.0092, 116.9631)
  line L15 (145, 115) -> (145.9908, 116.9631)
  line L16 (155, 102.5) -> (157, 103.2016)
  line L17 (157, 11.7984) -> (155, 12.5)
  line L18 (10, 0) -> (9.0388, -2)
  line L19 (-2, 103.2016) -> (0, 102.5)
  dimension "d34" = 2
  constraint coincident S0.end L5.start
  constraint coincident L4.end S0.start
  constraint coincident L3.end L4.start
  constraint coincident L2.end L3.start
  constraint coincident L0.end L1.start
  constraint coincident L5.end L6.start
extrude "Extrude2" add sketch "Sketch2" against normal blind 23 contours L0 L6 L7 L8 L18 L19 | L1 L2 L9 L10 L17 L18 | L5 L13 L14 L19 | S0 S1 L14 L15 | L3 L11 L16 L17 | L4 L12 L15 L16
sketch "Sketch3" plane through (0, 0, -20.5) normal (0, 0, -1) x (-1, 0, 0)
  line L0 (0, 102.5) -> (0, 12.5)
  line L1 (0, 12.5) -> (-10, 0)
  line L2 (-10, 0) -> (-145, 0)
  line L3 (-145, 0) -> (-155, 12.5)
  line L4 (-155, 12.5) -> (-155, 102.5)
  line L5 (-155, 102.5) -> (-145, 115)
  spline S0 degree 2 poles (-145, 115) (-77.5, 117.6157) (-10, 115) knots -13.5057 -13.5057 -13.5057 0 0 0 weights 1 3 1
  line L6 (-10, 115) -> (0, 102.5)
  line L7 (2, 103.2016) -> (-9.0092, 116.9631)
  spline S1 degree 3 poles (-9.0092, 116.9631) (-9.3137, 116.9749) (-9.6181, 116.9867) (-9.9226, 116.9985) (-14.5782, 117.1789) (-18.5002, 117.3289) (-21.9652, 117.4597) (-27.106, 117.6538) (-31.2439, 117.8059) (-34.8319, 117.9345) (-39.8791, 118.1155) (-43.8313, 118.2498) (-47.2448, 118.3599) (-51.5444, 118.4985) (-54.9693, 118.5979) (-57.9877, 118.6763) (-61.8549, 118.7768) (-65.0372, 118.8421) (-67.9652, 118.8866) (-71.9821, 118.9477) (-75.4974, 118.9695) (-79.1064, 118.9596) (-82.8964, 118.9491) (-86.738, 118.9044) (-91.4483, 118.8069) (-94.6262, 118.7412) (-98.1859, 118.6516) (-102.7172, 118.5165) (-106.1355, 118.4146) (-110.0914, 118.2873) (-115.2269, 118.109) (-118.9847, 117.9786) (-123.3639, 117.8212) (-128.9839, 117.6117) (-133.3735, 117.448) (-138.5067, 117.2531) (-145.0774, 116.9985) (-145.3819, 116.9867) (-145.6863, 116.9749) (-145.9908, 116.9631) knots -0.030457 -0.030457 -0.030457 -0.030457 0 0 0 0.465703 0.465703 0.465703 1.156627 1.156627 1.156627 2.128529 2.128529 2.128529 3.352707 3.352707 3.352707 4.921137 4.921137 4.921137 7.072806 7.072806 7.072806 9.332387 9.332387 9.332387 10.856885 10.856885 10.856885 12.006919 12.006919 12.006919 12.848427 12.848427 12.848427 13.5057 13.5057 13.5057 13.536157 13.536157 13.536157 13.536157
  line L8 (-145.9908, 116.9631) -> (-157, 103.2016)
  line L9 (-157, 103.2016) -> (-157, 11.7984)
  line L10 (-157, 11.7984) -> (-145.9612, -2)
  line L11 (-145.9612, -2) -> (-9.0388, -2)
  line L12 (-9.0388, -2) -> (2, 11.7984)
  line L13 (2, 11.7984) -> (2, 103.2016)
  line L14 (0, 102.5) -> (2, 103.2016)
  line L15 (-155, 102.5) -> (-157, 103.2016)
  constraint coincident L0.start L6.end
  constraint coincident L7.start L13.end
  constraint coincident L4.end L5.start
  constraint coincident L8.end L9.start
extrude "Extrude3" add sketch "Sketch3" along normal blind 25 contours L5 S0 L6 L7 S1 L8 L14 L15
sketch "Sketch4" plane through (-51.5617, 41.2494, 0) normal (-0.780869, 0.624695, 0) x (0, 0, 1)
  line L0 (2.5, 79.3375) -> (2.5, 96.9609)
  line L1 (2.5, 96.9609) -> (-45.5, 96.9609)
  line L2 (-45.5, 96.9609) -> (-45.5, 79.3375)
  line L3 (-45.5, 79.3375) -> (-20.5, 79.3375)
  line L4 (-20.5, 79.3375) -> (2.5, 79.3375)
  line L5 (-20.5, 79.3375) -> (-45.5, 95.9609)
  dimension "d39" = 1
  constraint coincident L3.end L4.start
  constraint coincident L2 L5.end
  measures "d39" distance of L1.end L5.end
extrude "Extrude4" cut sketch "Sketch4" against normal blind 4 contours L2 L3 L5
sketch "Sketch5" plane through (146.0739, 116.8591, 0) normal (0.780869, 0.624695, 0) x (0, 0, -1)
  line L0 (-2.5, 0.1331) -> (-2.5, -17.4902)
  line L1 (-2.5, -17.4902) -> (20.5, -17.4902)
  line L2 (20.5, -17.4902) -> (45.5, -17.4902)
  line L3 (45.5, -17.4902) -> (45.5, 0.1331)
  line L4 (45.5, 0.1331) -> (-2.5, 0.1331)
  line L5 (20.5, -17.4902) -> (45.5, -0.8669)
  dimension "d42" = 1
  constraint coincident L1.end L2.start
  constraint coincident L3 L5.end
  measures "d42" distance of L3.end L5.end
extrude "Extrude5" cut sketch "Sketch5" against normal blind 25 contours L2 L3 L5
sketch "Sketch6" plane through (0, 0, -20.5) normal (0, 0, -1) x (-1, 0, 0)
  line L0 (-155, 12.5) -> (-155, 102.5)
  line L1 (-155, 102.5) -> (-157, 103.2016)
  line L2 (-157, 103.2016) -> (-157, 11.7984)
  line L3 (-157, 11.7984) -> (-145.9612, -2)
  line L4 (-145.9612, -2) -> (-9.0388, -2)
  line L5 (-9.0388, -2) -> (2, 11.7984)
  line L6 (2, 11.7984) -> (2, 103.2016)
  line L7 (2, 103.2016) -> (0, 102.5)
  line L8 (0, 102.5) -> (0, 12.5)
  line L9 (0, 12.5) -> (-10, 0)
  line L10 (-10, 0) -> (-145, 0)
  line L11 (-145, 0) -> (-155, 12.5)
  line L12 (0, 12.5) -> (2, 12.5)
  line L13 (-155, 12.5) -> (-157, 12.5)
  constraint coincident L8.end L9.start
  constraint coincident L6 L12.end
  constraint perpendicular L6 L12
  constraint coincident L0.start L11.end
  constraint coincident L2 L13.end
  constraint perpendicular L2 L13
extrude "Extrude6" add sketch "Sketch6" along normal blind 15 contours L2 L3 L4 L5 L6 L9 L10 L11 L12 L13
sketch "Sketch7" plane through (6.0976, 4.878, 0) normal (0.780869, 0.624695, 0) x (0, 0, -1)
  line L0 (0, 9.7609) -> (0, -6.247)
  line L1 (0, -6.247) -> (35.5, -6.247)
  line L2 (35.5, -6.247) -> (35.5, 9.7609)
  line L3 (35.5, 9.7609) -> (20.5, 9.7609)
  line L4 (20.5, 9.7609) -> (0, 9.7609)
  line L5 (20.5, 9.7609) -> (35.5, -6.247)
  constraint coincident L3.end L4.start
  constraint coincident L1.end L2.start
extrude "Extrude7" cut sketch "Sketch7" against normal blind 13.5 contours L2 L3 L5
sketch "Sketch8" plane through (88.4146, -70.7317, 0) normal (-0.780869, 0.624695, 0) x (0, 0, 1)
  line L0 (0, 90.5808) -> (0, 106.5886)
  line L1 (0, 106.5886) -> (-20.5, 106.5886)
  line L2 (-20.5, 106.5886) -> (-35.5, 106.5886)
  line L3 (-35.5, 106.5886) -> (-35.5, 90.5808)
  line L4 (-35.5, 90.5808) -> (0, 90.5808)
  line L5 (-20.5, 106.5886) -> (-35.5, 90.5808)
  constraint coincident L1.end L2.start
  constraint coincident L3.end L4.start
extrude "Extrude8" cut sketch "Sketch8" against normal blind 11 contours L2 L3 L5
extrude "Extrude9" cut 1 faces at (-1.1872, 12.0835, -35.5) along direction (0, 0, 1) blind 15
extrude "Extrude10" cut 1 faces at (156.1872, 12.0835, -35.5) along direction (0, 0, 1) blind 15
sketch "Sketch9" plane through (-2, 0, 0) normal (-1, 0, 0) x (0, 0, 1)
  line L0 (-20.5, 103.2016) -> (-20.5, 11.7984)
  line L1 (-20.5, 11.7984) -> (2.5, 11.7984)
  line L2 (2.5, 11.7984) -> (2.5, 103.2016)
  line L3 (2.5, 103.2016) -> (-20.5, 103.2016)
  line L4 (-20.5, 69.9984) -> (-20.5, 44.9984)
  line L5 (-20.5, 69.9984) -> (-9.2237, 65.8942)
  line L6 (-20.5, 69.9984) -> (-8.5, 69.9984) construction
  line L7 (-20.5, 44.9984) -> (-9.2237, 49.1027)
  line L8 (-20.5, 44.9984) -> (-8.5, 44.9984) construction
  line L9 (-9.2237, 65.8942) -> (-9.2237, 49.1027)
  dimension "d55" = 25
  dimension "d56" = 33.2
  dimension "d57" = 20
  dimension "d58" = 12
  dimension "d59" = 12
  dimension "d60" = 20
  constraint coincident L0 L4.start
  constraint perpendicular L3 L4
  constraint horizontal L6
  constraint horizontal L8
  measures "d55" distance of L4.start L4.end
  measures "d56" distance of L0.end L4.end
  measures "d57" angle of L5 L6
  measures "d58" distance of L4.start L5.end
  measures "d59" distance of L4.end L7.end
  measures "d60" angle of L7 L8
extrude "Extrude11" cut sketch "Sketch9" against normal blind 6 contours L0 L4 L5 L7 L9
sketch "Sketch10" plane through (157, 0, 0) normal (1, 0, 0) x (0, 0, -1)
  line L0 (20.5, 11.7984) -> (20.5, 12.5)
  line L1 (20.5, 12.5) -> (20.5, 103.2016)
  line L2 (20.5, 103.2016) -> (-2.5, 103.2016)
  line L3 (-2.5, 103.2016) -> (-2.5, 11.7984)
  line L4 (-2.5, 11.7984) -> (20.5, 11.7984)
  line L5 (20.5, 69.9984) -> (20.5, 44.9984)
  line L6 (20.5, 44.9984) -> (9.2237, 49.1027)
  line L7 (20.5, 69.9984) -> (9.2237, 65.8942)
  line L8 (20.5, 69.9984) -> (6.5392, 69.9984) construction
  line L9 (20.5, 44.9984) -> (8, 44.9984) construction
  line L10 (9.2237, 65.8942) -> (9.2237, 49.1027)
  dimension "d63" = 25
  dimension "d64" = 33.2
  dimension "d65" = 12
  dimension "d66" = 12
  dimension "d67" = 20
  dimension "d68" = 20
  constraint coincident L1 L5.start
  constraint coincident L1 L5.end
  constraint perpendicular L5 L8
  constraint perpendicular L1 L9
  measures "d63" distance of L5.start L5.end
  measures "d64" distance of L0.start L5.end
  measures "d65" distance of L5.end L6.end
  measures "d66" distance of L5.start L7.end
  measures "d67" angle of L7 L8
  measures "d68" angle of L6 L9
extrude "Extrude12" cut sketch "Sketch10" against normal blind 3 contours L1 L5 L6 L7 L10
sketch "Sketch11" plane through (0, 0, 0) normal (0, 0, -1) x (-1, 0, 0)
  line L0 (-10, 0) -> (0, 12.5)
  line L1 (0, 12.5) -> (0, 102.5)
  line L2 (0, 102.5) -> (-10, 115)
  spline S0 degree 2 poles (-10, 115) (-77.5, 117.6157) (-145, 115) knots 0 0 0 13.5057 13.5057 13.5057 weights 1 3 1
  line L3 (-145, 115) -> (-155, 102.5)
  line L4 (-155, 102.5) -> (-155, 12.5)
  line L5 (-155, 12.5) -> (-145, 0)
  line L6 (-145, 0) -> (-10, 0)
  line L7 (-140, 103) -> (-90, 103) construction
  line L8 (-90, 103) -> (-90, 71) construction
  line L9 (-90, 71) -> (-140, 71) construction
  line L10 (-140, 71) -> (-140, 103) construction
  line L11 (-15, 103) -> (-65, 103) construction
  line L12 (-65, 103) -> (-65, 71) construction
  line L13 (-65, 71) -> (-15, 71) construction
  line L14 (-15, 71) -> (-15, 103) construction
  line L15 (-110.5, 12) -> (-78.5, 12) construction
  line L16 (-78.5, 12) -> (-78.5, 62) construction
  line L17 (-78.5, 62) -> (-110.5, 62) construction
  line L18 (-110.5, 62) -> (-110.5, 12) construction
  line L19 (-44.5, 12) -> (-76.5, 12) construction
  line L20 (-76.5, 12) -> (-76.5, 62) construction
  line L21 (-76.5, 62) -> (-44.5, 62) construction
  line L22 (-44.5, 62) -> (-44.5, 12) construction
  circle A0 centre (-107.5, 59) radius 2.5
  circle A1 centre (-107.5, 15) radius 2.5
  line L23 (-94.5, 62) -> (-94.5, 12) construction
  circle A2 centre (-81.5, 59) radius 2.5
  circle A3 centre (-81.5, 15) radius 2.5
  circle A4 centre (-137, 100) radius 2.5
  circle A5 centre (-137, 74) radius 2.5
  line L24 (-115, 103) -> (-115, 71) construction
  line L25 (-40, 103) -> (-40, 71) construction
  circle A6 centre (-62, 100) radius 2.5
  circle A7 centre (-62, 74) radius 2.5
  circle A8 centre (-73.5, 59) radius 2.5
  circle A9 centre (-73.5, 15) radius 2.5
  circle A10 centre (-93, 100) radius 2.5
  circle A11 centre (-93, 74) radius 2.5
  circle A12 centre (-18, 100) radius 2.5
  circle A13 centre (-18, 74) radius 2.5
  line L26 (-60.5, 62) -> (-60.5, 12) construction
  circle A14 centre (-47.5, 59) radius 2.5
  circle A15 centre (-47.5, 15) radius 2.5
  circle A16 centre (-93, 100) radius 1.25
  circle A17 centre (-137, 100) radius 1.25
  circle A18 centre (-93, 74) radius 1.25
  circle A19 centre (-137, 74) radius 1.25
  circle A20 centre (-62, 100) radius 1.25
  circle A21 centre (-62, 74) radius 1.25
  circle A22 centre (-18, 74) radius 1.25
  circle A23 centre (-18, 100) radius 1.25
  circle A24 centre (-107.5, 59) radius 1.25
  circle A25 centre (-81.5, 59) radius 1.25
  circle A26 centre (-81.5, 15) radius 1.25
  circle A27 centre (-107.5, 15) radius 1.25
  circle A28 centre (-73.5, 15) radius 1.25
  circle A29 centre (-73.5, 59) radius 1.25
  circle A30 centre (-47.5, 59) radius 1.25
  circle A31 centre (-47.5, 15) radius 1.25
  dimension "d71" = 50
  dimension "d72" = 32
  dimension "d73" = 50
  dimension "d74" = 32
  dimension "d75" = 32
  dimension "d76" = 50
  dimension "d77" = 50
  dimension "d78" = 2
  dimension "d81" = 32
  dimension "d82" = 12
  dimension "d83" = 44.5
  dimension "d84" = 12
  dimension "d85" = 12
  dimension "d86" = 5
  dimension "d87" = 5
  dimension "d88" = 3
  dimension "d89" = 3
  dimension "d90" = 3
  dimension "d91" = 3
  dimension "d92" = 5
  dimension "d93" = 5
  dimension "d94" = 5
  dimension "d95" = 5
  dimension "d96" = 5
  dimension "d97" = 5
  dimension "d98" = 3
  dimension "d99" = 3
  dimension "d100" = 3
  dimension "d101" = 3
  dimension "d102" = 3
  dimension "d103" = 3
  dimension "d104" = 3
  dimension "d105" = 3
  dimension "d106" = 3
  dimension "d107" = 3
  dimension "d108" = 3
  dimension "d109" = 3
  dimension "d112" = -1.25
  dimension "d113" = -1.25
  dimension "d114" = -1.25
  dimension "d115" = -1.25
  dimension "d116" = -1.25
  dimension "d117" = -1.25
  dimension "d118" = -1.25
  dimension "d119" = -1.25
  dimension "d120" = -1.25
  dimension "d121" = -1.25
  dimension "d122" = -1.25
  dimension "d123" = -1.25
  dimension "d124" = -1.25
  dimension "d125" = -1.25
  dimension "d126" = -1.25
  dimension "d127" = -1.25
  constraint horizontal L7
  constraint vertical L8
  constraint horizontal L9
  constraint vertical L10
  constraint horizontal L11
  constraint vertical L12
  constraint horizontal L13
  constraint vertical L14
  constraint horizontal L15
  constraint vertical L16
  constraint horizontal L17
  constraint vertical L18
  constraint horizontal L19
  constraint vertical L20
  constraint horizontal L21
  constraint vertical L22
  constraint midpoint L17 L23.start
  constraint midpoint L15 L23.end
  constraint symmetric A0 L23 A2
  constraint symmetric A1 L23 A3
  constraint midpoint L7 L24.start
  constraint midpoint L9 L24.end
  constraint midpoint L11 L25.start
  constraint midpoint L13 L25.end
  constraint symmetric A4 L24 A10
  constraint symmetric A5 L24 A11
  constraint symmetric L25 A6 A12
  constraint symmetric L25 A7 A13
  constraint midpoint L21 L26.start
  constraint midpoint L19 L26.end
  constraint symmetric A8 L26 A14
  constraint symmetric A9 L26 A15
  measures "d71" distance of L7.start L7.end
  measures "d72" distance of L7.start L9.end
  measures "d73" distance of L11.start L11.end
  measures "d74" distance of L11.start L13.end
  measures "d75" distance of L15.start L15.end
  measures "d76" distance of L15.start L17.end
  measures "d77" distance of L19.start L21.end
  measures "d78" distance of L16 L20
  measures "d81" distance of L19.start L19.end
  measures "d82" distance of L6 L19
  measures "d83" distance of L4 L18
  measures "d84" distance of S0.end L7
  measures "d85" distance of L2.end L11
  measures "d86" diameter of A0
  measures "d87" diameter of A1
  measures "d88" distance of L18 A0.centre
  measures "d89" distance of L17 A0.centre
  measures "d90" distance of L18 A1.centre
  measures "d91" distance of L15 A1.centre
  measures "d92" diameter of A4
  measures "d93" diameter of A5
  measures "d94" diameter of A6
  measures "d95" diameter of A7
  measures "d96" diameter of A8
  measures "d97" diameter of A9
  measures "d98" distance of L7 A4.centre
  measures "d99" distance of L10 A4.centre
  measures "d100" distance of L9 A5.centre
  measures "d101" distance of L10 A5.centre
  measures "d102" distance of L11 A6.centre
  measures "d103" distance of L12 A6.centre
  measures "d104" distance of L13 A7.centre
  measures "d105" distance of L12 A7.centre
  measures "d106" distance of L21 A8.centre
  measures "d107" distance of L20 A8.centre
  measures "d108" distance of L19 A9.centre
  measures "d109" distance of L20 A9.centre
extrude "Extrude14" add sketch "Sketch11" along normal blind 8 contours A0 | A1 | A2 | A3 | A4 | A5 | A6 | A7 | A8 | A9 | A10 | A11 | A12 | A13 | A14 | A15
sketch "Sketch12" plane through (0, 0, 0) normal (0, 0, -1) x (-1, 0, 0)
  line L0 (-145, 40) -> (-125, 40)
  line L1 (-125, 40) -> (-125, 20)
  line L2 (-125, 20) -> (-145, 20)
  line L3 (-145, 20) -> (-145, 40)
  constraint horizontal L0
  constraint vertical L1
  constraint horizontal L2
  constraint vertical L3
extrude "Extrude15" cut sketch "Sketch12" against normal blind 5
sketch "Sketch13" plane through (0, 0, 0) normal (0, 0, -1) x (-1, 0, 0)
  circle A0 centre (-137, 100) radius 2.5
  circle A1 centre (-107.5, 59) radius 2.5
  circle A2 centre (-107.5, 15) radius 2.5
  circle A3 centre (-93, 74) radius 2.5
  circle A4 centre (-93, 100) radius 2.5
  circle A5 centre (-81.5, 59) radius 2.5
  circle A6 centre (-81.5, 15) radius 2.5
  circle A7 centre (-62, 74) radius 2.5
  line L0 (-10, 0) -> (0, 12.5)
  line L1 (0, 12.5) -> (0, 102.5)
  line L2 (0, 102.5) -> (-10, 115)
  spline S0 degree 2 poles (-10, 115) (-77.5, 117.6157) (-145, 115) knots 0 0 0 13.5057 13.5057 13.5057 weights 1 3 1
  line L3 (-145, 115) -> (-155, 102.5)
  line L4 (-155, 102.5) -> (-155, 12.5)
  line L5 (-155, 12.5) -> (-145, 0)
  line L6 (-145, 0) -> (-10, 0)
  circle A8 centre (-62, 100) radius 2.5
  circle A9 centre (-73.5, 59) radius 2.5
  circle A10 centre (-73.5, 15) radius 2.5
  circle A11 centre (-137, 74) radius 2.5
  circle A12 centre (-18, 100) radius 2.5
  circle A13 centre (-47.5, 59) radius 2.5
  circle A14 centre (-47.5, 15) radius 2.5
  circle A15 centre (-18, 74) radius 2.5
  line L7 (-125, 40) -> (-125, 20)
  line L8 (-125, 20) -> (-145, 20)
  line L9 (-145, 20) -> (-145, 40)
  line L10 (-145, 40) -> (-125, 40)
  circle A16 centre (-35, 68) radius 2.5
  dimension "d132" = 5
  dimension "d133" = 35
  dimension "d134" = 68
  measures "d132" diameter of A16
  measures "d133" distance of L1 A16.centre
  measures "d134" distance of L6 A16.centre
extrude "Extrude16" cut sketch "Sketch13" against normal blind 10 contours A16